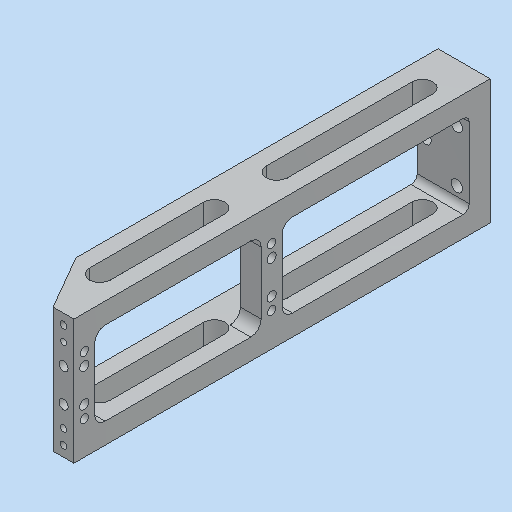
# Autodesk Inventor part: MM0948AN002_G01_110
Saved by Autodesk Inventor 2023.3 (Build 273359000, 359)
## iProperties
Created: 2023-03-23
Part Number: MM0948AN002_G01_110
Material: 3.3547 AlMg4,5Mn0,7 - AW 5083
Description: =<RBPARTNOTITLE2>
Document SubType Name: Modeling
Designer: ric7an
Mass: 223.477 g
Surface Area: 352.778 cm^2
Volume: 84.0141 cm^3
Density: 2.66 g/cm^3
Appearance: Aluminium AnP
AnP_Kategorie: 1
AnP_Material: =<Material>
MaxAbmaße: 75 x 200 x 25 (FM)
AnP_TemplVers: 20200821
RBDOCUMENTTYPE: DRF
RBDOCUMENTVERSION: 00
RBDRAWINGMAINSCALE: 1:1
RBDRAWINGMISSINGSPEC: --
RBDRAWINGVOLUME: --
RBDSV1: 0850
RBGBEDGESIN1: +0,5
RBGBEDGESIN2: +0,2
RBGBEDGESOUT1: -0,3
RBGBEDGESOUT2: -0,1
RBMATERIAL: =<Material>
RBMATMEETS: --
RBMATNO: =<Part Number>
RBPARTMADEOF: 75 x 200 x 25 (FM)
RBPARTNO: SIEHE MNR
RBPARTNOTITLE1: manufactured part
RBPARTNOTITLE2: Anfertigungsteil
RBPARTSAFETYINDICATOR: --
RBSURFACE: anodised colourless
RBSURFACE2: eloxiert farblos
RBZEDGESNORM: ISO13715:2002-06
RBZGENDIMCLASS: m
RBZGENDIMNORM: ISO 2768-1:1989-11
RBZGENGEOCLASS: H
RBZGENGEONORM: ISO 2768-2:1989-11
RBZSURFACENORM: ISO13D2:2002-02
RBZTOLERANCENORM: ISO 14405-1:2010-12
AnP_Kommentar_aktuell: =<Comments>
AnP_Material_aktuell: =<Material>
Author: FH/Wi
Keywords: =<RBPARTMADEOF>
Comments: =<RBSURFACE2>
Revision Number: 01
Autodesk Inventor part; units mm, degrees
ref_plane "YZ Plane" through (0, 0, 0) normal (1, 0, 0) x (0, 1, 0)
ref_plane "XZ Plane" through (0, 0, 0) normal (0, 1, 0) x (-1, 0, 0)
ref_plane "XY Plane" through (0, 0, 0) normal (0, 0, 1) x (1, 0, 0)
sketch "Skizze1" plane through (0, 0, 0) normal (0, 0, 1) x (1, 0, 0)
  line L0 (0, 0) -> (25, 0)
  line L1 (25, 0) -> (25, 200)
  line L2 (25, 200) -> (0, 200)
  line L3 (0, 200) -> (0, 0)
  line L4 (0, 190) -> (15, 190)
  line L5 (15, 190) -> (15, 0)
  line L6 (15, 0) -> (0, 0)
  line L7 (0, 0) -> (0, 190)
  dimension "d0" = 25
  dimension "d2" = 10
  dimension "d3" = 10
  dimension "d4" = 200
  constraints: 16 end point, 4 parallel, 2 horizontal, 2 perpendicular, 2 point on line
  measures "d0" distance of L1.end L2.end
  measures "d2" distance between parallel lines of L4 L2
  measures "d3" distance between parallel lines of L1 L5
  measures "d4" distance between parallel lines of L0 L2
extrude "Extrusion1" add sketch "Skizze1" along normal mid plane 60 contours L5 L4 L3 L2 L1 L0
sketch "Skizze2" plane through (15, 0, 30) normal (-1, 0, 0) x (0, 0, 1)
  line L0 (-60, 0) -> (0, 0) projected
  line L1 (0, 190) -> (0, 0) projected
  line L2 (-60, 190) -> (0, 190) projected
  line L3 (-60, 0) -> (-60, 190) projected
  line L4 (-50, 190) -> (-10, 190)
  line L5 (-10, 190) -> (-10, 100)
  line L6 (-10, 100) -> (-50, 100)
  line L7 (-50, 100) -> (-50, 190)
  line L8 (-50, 90) -> (-10, 90)
  line L9 (-10, 90) -> (-10, 10)
  line L10 (-10, 10) -> (-50, 10)
  line L11 (-50, 10) -> (-50, 90)
  line L12 (-30, 240) -> (-30, -40) projected
  point P0 (-30, 0)
  dimension "d7" = 0
  dimension "d8" = 10
  dimension "d9" = 10
  dimension "d10" = 90
  dimension "d11" = 10
  constraints: 16 end point, 4 parallel, 2 horizontal, 2 perpendicular, 1 collinear, 2 other
  measures "d7" distance between parallel lines of L2 L4
  measures "d8" distance between parallel lines of L8 L6
  measures "d9" distance between parallel lines of L0 L10
  measures "d10" distance between parallel lines of L0 L8
  measures "d11" distance between parallel lines of L1 L5
extrude "Extrusion2" cut sketch "Skizze2" against normal blind 10 contours L12 L8 L9 L10 | L10 L11 L8 L12 | L2 L12 L6 L7 | L2 L5 L6 L12
sketch "Skizze3" plane through (0, 190, 30) normal (0, -1, 0) x (1, 0, 0)
  line L0 (0, 12) -> (0, -72) projected
  line L1 (-5, -30) -> (30, -30) projected
  line L2 (15, -60) -> (15, 0) projected
  line L3 (25, -60) -> (25, 0) projected
  point P0 (0, -30)
  point P1 (19, -17.5)
  point P2 (19, -42.5)
  point P3 (4, -30)
  dimension "d14" = 25
  dimension "d26" = 6
  dimension "d27" = 15
  constraints: 1 point on line, 1 symmetric about line
  measures "d14" distance of point (19, -42.5) point (19, -17.5)
  measures "d26" distance from line of L3 point (19, -17.5)
  measures "d27" horizontal distance of point (4, -30) point (19, -17.5)
hole "Bohrung1" at (19, 190, 12.5) at (19, 190, -12.5) at (4, 190, 0) direction (0, 1, 0) diameter 5.5 end through all clearance for "Inbusschraube ISO 4762  versenkt" size "M5" standard "ISO"
sketch "Skizze4" plane through (15, 0, 30) normal (-1, 0, 0) x (0, 0, 1)
  line L0 (-10, 90) -> (-10, 10) projected
  line L1 (-10, 10) -> (-50, 10) projected
  line L2 (-50, 10) -> (-50, 90) projected
  line L3 (-50, 90) -> (-10, 90) projected
  line L4 (-50, 100) -> (-50, 190) projected
  line L5 (-10, 190) -> (-10, 100) projected
  line L6 (-10, 100) -> (-50, 100) projected
  line L7 (-60, 0) -> (0, 0) projected
  line L8 (0, 190) -> (0, 0) projected
  line L9 (-60, 190) -> (-50, 190) projected
  line L10 (-60, 0) -> (-60, 190) projected
  line L11 (-60, 190) -> (-50, 190)
  line L12 (-50, 190) -> (-50, 0)
  line L13 (-50, 0) -> (-60, 0)
  line L14 (-60, 0) -> (-60, 190)
  line L15 (0, 190) -> (-10, 190)
  line L16 (-10, 190) -> (-10, 0)
  line L17 (-10, 0) -> (0, 0)
  line L18 (0, 0) -> (0, 190)
  line L19 (-10, 190) -> (0, 190) projected
  point P0 (-30, 0)
  point P1 (-10, 200)
  point P2 (-10, 100)
  constraints: 16 end point, 4 parallel, 2 collinear, 2 horizontal, 2 perpendicular, 2 point on line
extrude "Extrusion3" add sketch "Skizze4" along normal up to surface (15 mm away) contours L16 L5 L15 L8 L7 L0 | L2 L12 L7 L10 L9 L4
chamfer "Fase1" distance 15 angle 60 1 edges at (0, 0, 25) measured on face at (0.5, 0, 25)
sketch "Skizze5" plane through (0, 0, 30) normal (0, 0, 1) x (1, 0, 0)
  line L0 (12.5, 180) -> (12.5, 110) construction
  line L1 (7.5, 180) -> (7.5, 110)
  line L2 (17.5, 110) -> (17.5, 180)
  arc A0 (17.5, 180) -> (7.5, 180) centre (12.5, 180) ccw
  arc A1 (7.5, 110) -> (17.5, 110) centre (12.5, 110) ccw
  line L3 (12.5, 80) -> (12.5, 25) construction
  line L4 (7.5, 80) -> (7.5, 25)
  line L5 (17.5, 25) -> (17.5, 80)
  arc A2 (17.5, 80) -> (7.5, 80) centre (12.5, 80) ccw
  arc A3 (7.5, 25) -> (17.5, 25) centre (12.5, 25) ccw
  line L6 (25, 0) -> (25, 200) projected
  line L7 (25, 0) -> (0, 0) projected
  line L8 (15, 100) -> (25, 100) projected
  line L9 (15, 90) -> (25, 90) projected
  line L10 (15, 10) -> (25, 10) projected
  point P0 (12.5, 145)
  point P1 (12.5, 52.5)
  point P2 (15, 0)
  point P3 (25, 190)
  point P4 (0, 200)
  dimension "d32" = 12.5
  dimension "d33" = 10
  dimension "d34" = 55
  dimension "d36" = 70
  dimension "d37" = 42.5
  dimension "d38" = 45
  constraints: 16 end point, 8 point on circle, 8 tangent, 4 centre point, 2 midpoint, 2 parallel, 2 point on line, 1 collinear, 1 vertical, 1 other
  measures "d32" distance between parallel lines of L6 L0
  measures "d33" distance between parallel lines of L2 L1
  measures "d34" distance of L5.start L5.end
  measures "d36" distance of L2.start L2.end
  measures "d37" distance from line of L10 point (12.5, 52.5)
  measures "d38" distance from line of L8 point (12.5, 145)
extrude "Extrusion4" cut sketch "Skizze5" against normal through all
chamfer "Fase2" distance 15 angle 60 1 edges at (0, 0, -25) measured on face at (0.5, 0, -25)
fillet "Rundung1" radius 5 6 edges at (20, 10, 20) (20, 10, -20) (20, 90, 20) (20, 90, -20) (20, 100, -20) (20, 100, 20)
sketch "Skizze6" plane through (15, 85, 20) normal (-1, 0, 0) x (0, 0, 1)
  line L0 (-20, 155) -> (-20, -125) projected
  line L1 (-5, 15) -> (-35, 15) projected
  line L2 (-40, -85) -> (0, -85) projected
  point P0 (-20, -85)
  point P1 (-28, 10)
  point P2 (-12, 10)
  point P3 (-12, -80)
  point P4 (-28, -80)
  dimension "d45" = 16
  dimension "d53" = 5
  dimension "d54" = 5
  constraints: 2 horizontal alignment, 1 vertical alignment, 1 other
  measures "d45" distance of point (-12, 10) point (-28, 10)
  measures "d53" distance from line of L1 point (-28, 10)
  measures "d54" distance from line of L2 point (-28, -80)
hole "Bohrung2" at (15, 95, -8) at (15, 95, 8) at (15, 5, 8) at (15, 5, -8) direction (1, 0, 0) diameter 4.5 end through all clearance for "Inbusschraube ISO 4762  versenkt" size "M4" standard "ISO"
fillet "Rundung3" radius 3 2 edges at (12.5, 190, 20) (12.5, 190, -20)
sketch "Skizze7" plane through (25, 0, 30) normal (1, 0, 0) x (0, 0, -1)
  line L0 (30, -40) -> (30, 240) projected
  circle A0 centre (22, 95) radius 2.25 projected
  circle A1 centre (22, 5) radius 2.25 projected
  point P0 (30, 0)
  point P1 (16, 95)
  point P2 (44, 95)
  point P3 (16, 5)
  point P4 (44, 5)
  dimension "d57" = 28
  constraints: 2 horizontal alignment, 2 symmetric about line, 1 vertical alignment
  measures "d57" distance of point (44, 95) point (16, 95)
hole "Bohrung3" at (25, 95, 14) at (25, 95, -14) at (25, 5, 14) at (25, 5, -14) direction (-1, 0, 0) diameter 4 end through all
sketch "Skizze8" plane through (25, 0, -30) normal (0, -1, 0) x (1, 0, 0)
  line L0 (-30, 30) -> (5, 30) projected
  line L1 (0, 0) -> (0, 60) projected
  line L2 (0, 60) -> (-10, 60) projected
  point P0 (-25, 30)
  point P1 (-5, 55)
  point P2 (-5, 5)
  point P3 (-5, 38)
  point P4 (-5, 22)
  point P5 (-5, 48)
  point P6 (-5, 12)
  dimension "d65" = 5
  dimension "d66" = 5
  dimension "d67" = 7
  dimension "d68" = 16
  constraints: 3 symmetric about line, 2 vertical alignment
  measures "d65" distance from line of L1 point (-5, 38)
  measures "d66" distance from line of L2 point (-5, 55)
  measures "d67" distance of point (-5, 48) point (-5, 55)
  measures "d68" distance of point (-5, 22) point (-5, 38)
hole "Bohrung4" at (20, 0, 8) at (20, 0, -8) direction (0, 1, 0) diameter 4.5 depth 10 clearance for "Inbusschraube ISO 4762  versenkt" size "M4" standard "ISO"
hole "Bohrung5" at (20, 0, 18) at (20, 0, -18) direction (0, 1, 0) diameter 3 depth 8 tip angle 118
hole "Bohrung6" at (20, 0, 25) at (20, 0, -25) direction (0, 1, 0) diameter 3.242 depth 11.8 tip angle 118 thread size "M4x0.7" designation "M4" class "6H" standard "ISO Metric profile"
